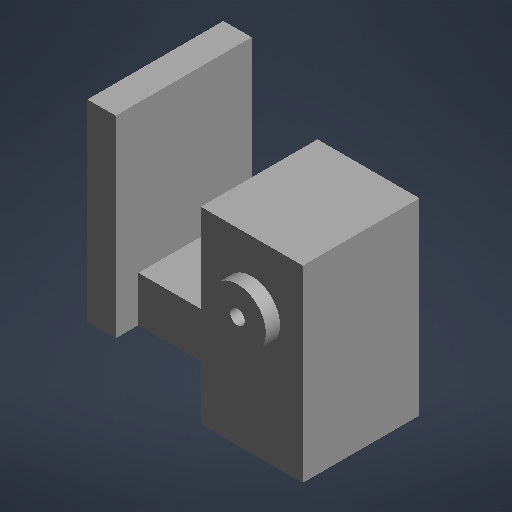
# Autodesk Inventor part: R2_hombro_izq
Saved by Autodesk Inventor 2027 (Build 310192060, 192F)
## iProperties
Part Number: R2_hombro_izq
Material: Genérico
Document SubType Name: Modelado
Designer: rodri
Appearance: Por defecto
Author: rodri
Autodesk Inventor part; units mm, degrees
ref_plane "Plano de trabajo1" through (0, 0, -12) normal (0, 0, 1) x (1, 0, 0)
sketch "Boceto1" plane through (0, 0, -12) normal (0, 0, 1) x (1, 0, 0)
  line L0 (49.51, 31) -> (54.5, 31)
  line L1 (54.5, 31) -> (54.5, 65)
  line L2 (54.5, 65) -> (49.51, 65)
  line L3 (49.51, 65) -> (49.51, 31)
  constraints: 8 end point, 2 parallel, 1 horizontal, 1 perpendicular
extrude "Extrusión1" add sketch "Boceto1" along normal blind 24
ref_plane "Plano de trabajo2" through (49.51, 0, 0) normal (1, 0, 0) x (0, 1, 0)
sketch "Boceto2" plane through (49.51, 0, 0) normal (1, 0, 0) x (0, 1, 0)
  circle A0 centre (53, 0) radius 12
  constraints: 1 centre point
extrude "Extrusión2" add sketch "Boceto2" along normal blind 4.99
ref_plane "Plano de trabajo3" through (0, 0, -3.1) normal (0, 0, 1) x (1, 0, 0)
sketch "Boceto3" plane through (0, 0, -3.1) normal (0, 0, 1) x (1, 0, 0)
  line L0 (75, 30.9) -> (93, 30.9)
  line L1 (93, 30.9) -> (93, 64.1)
  line L2 (93, 64.1) -> (75, 64.1)
  line L3 (75, 64.1) -> (75, 30.9)
  constraints: 8 end point, 2 parallel, 1 horizontal, 1 perpendicular
extrude "Extrusión3" add sketch "Boceto3" along normal blind 20.6
ref_plane "Plano de trabajo4" through (0, 0, -3.2) normal (0, 0, 1) x (1, 0, 0)
sketch "Boceto4" plane through (0, 0, -3.2) normal (0, 0, 1) x (1, 0, 0)
  line L0 (77.5, 35.7) -> (90.5, 35.7)
  line L1 (90.5, 35.7) -> (90.5, 59.3)
  line L2 (90.5, 59.3) -> (77.5, 59.3)
  line L3 (77.5, 59.3) -> (77.5, 35.7)
  constraints: 8 end point, 2 parallel, 1 horizontal, 1 perpendicular
extrude "Extrusión4" cut sketch "Boceto4" along normal blind 18.2
ref_plane "Plano de trabajo5" through (0, 0, 10) normal (0, 0, 1) x (1, 0, 0)
sketch "Boceto5" plane through (0, 0, 10) normal (0, 0, 1) x (1, 0, 0)
  line L0 (80.5, 30.5) -> (87.5, 30.5)
  line L1 (87.5, 30.5) -> (87.5, 37.5)
  line L2 (87.5, 37.5) -> (80.5, 37.5)
  line L3 (80.5, 37.5) -> (80.5, 30.5)
  constraints: 8 end point, 2 parallel, 1 horizontal, 1 perpendicular
extrude "Extrusión5" cut sketch "Boceto5" along normal blind 5
ref_plane "Plano de trabajo6" through (0, 0, -3.2) normal (0, 0, 1) x (1, 0, 0)
sketch "Boceto6" plane through (0, 0, -3.2) normal (0, 0, 1) x (1, 0, 0)
  circle A0 centre (84, 33.6) radius 0.85
  constraints: 1 centre point
extrude "Extrusión6" cut sketch "Boceto6" along normal blind 6.1
ref_plane "Plano de trabajo7" through (0, 0, -3.2) normal (0, 0, 1) x (1, 0, 0)
sketch "Boceto7" plane through (0, 0, -3.2) normal (0, 0, 1) x (1, 0, 0)
  circle A0 centre (84, 61.4) radius 0.85
  constraints: 1 centre point
extrude "Extrusión7" cut sketch "Boceto7" along normal blind 6.1
ref_plane "Plano de trabajo8" through (0, 0, 17.49) normal (0, 0, 1) x (1, 0, 0)
sketch "Boceto8" plane through (0, 0, 17.49) normal (0, 0, 1) x (1, 0, 0)
  circle A0 centre (84, 53) radius 5
  constraints: 1 centre point
extrude "Extrusión8" add sketch "Boceto8" along normal blind 2.51
ref_plane "Plano de trabajo9" through (0, 0, 15.6) normal (0, 0, 1) x (1, 0, 0)
sketch "Boceto9" plane through (0, 0, 15.6) normal (0, 0, 1) x (1, 0, 0)
  circle A0 centre (84, 53) radius 1.3
  constraints: 1 centre point
extrude "Extrusión9" cut sketch "Boceto9" along normal blind 4.5
ref_plane "Plano de trabajo10" through (0, 0, -8) normal (0, 0, 1) x (1, 0, 0)
sketch "Boceto10" plane through (0, 0, -8) normal (0, 0, 1) x (1, 0, 0)
  line L0 (54.5, 31) -> (75, 31)
  line L1 (75, 31) -> (75, 39)
  line L2 (75, 39) -> (54.5, 39)
  line L3 (54.5, 39) -> (54.5, 31)
  constraints: 8 end point, 2 parallel, 1 horizontal, 1 perpendicular
extrude "Extrusión10" add sketch "Boceto10" along normal blind 16
ref_plane "Plano de trabajo11" through (49.4, 0, 0) normal (1, 0, 0) x (0, 1, 0)
sketch "Boceto11" plane through (49.4, 0, 0) normal (1, 0, 0) x (0, 1, 0)
  circle A0 centre (53, 0) radius 4.2
  constraints: 1 centre point
extrude "Extrusión11" cut sketch "Boceto11" along normal blind 2.1
